Autodesk Fusion 360 part; units mm, degrees
(part 4 of 4)
ref_plane "工作平面8" through (0, 0, 210) normal (0, 0, 1) x (1, 0, 0) in component "10_CPU_140_FAN_MOUNT"
sketch "草图8 (20)" plane through (0, 0, 210) normal (0, 0, 1) x (1, 0, 0) in component "10_CPU_140_FAN_MOUNT"
  circle A0 centre (176.4, -14) radius 1.7
extrude "M3x6 fan panel tab clearance'" cut sketch "草图8 (20)" along normal blind 3.01 bodies 2 in component "10_CPU_140_FAN_MOUNT"
ref_plane "工作平面18" through (0, 0, 148) normal (0, 0, 1) x (1, 0, 0) in component "20_ONE_PIECE_DUAL_140_FAN_RAIL_284mm"
sketch "草图18 (3)" plane through (0, 0, 148) normal (0, 0, 1) x (1, 0, 0) in component "20_ONE_PIECE_DUAL_140_FAN_RAIL_284mm"
  line L0 (170.4, -19) -> (182.4, -19)
  line L1 (182.4, -19) -> (182.4, -9)
  line L2 (182.4, -9) -> (170.4, -9)
  line L3 (170.4, -9) -> (170.4, -19)
extrude "Integral fan panel tab support pad (2)" add sketch "草图18 (3)" along normal blind 12 bodies 35 in component "20_ONE_PIECE_DUAL_140_FAN_RAIL_284mm"
ref_plane "工作平面19" through (0, 0, 153.5) normal (0, 0, 1) x (1, 0, 0) in component "20_ONE_PIECE_DUAL_140_FAN_RAIL_284mm"
sketch "草图19 (3)" plane through (0, 0, 153.5) normal (0, 0, 1) x (1, 0, 0) in component "20_ONE_PIECE_DUAL_140_FAN_RAIL_284mm"
  circle A0 centre (176.4, -14) radius 2.35
extrude "H4.5 insert for fan panel M3x6 fastening (2)" cut sketch "草图19 (3)" along normal blind 6.51 bodies 35 in component "20_ONE_PIECE_DUAL_140_FAN_RAIL_284mm"
ref_plane "工作平面9" through (0, 0, 210) normal (0, 0, 1) x (1, 0, 0) in component "10_CPU_140_FAN_MOUNT"
sketch "草图9 (20)" plane through (0, 0, 210) normal (0, 0, 1) x (1, 0, 0) in component "10_CPU_140_FAN_MOUNT"
  line L0 (270.4, -19) -> (282.4, -19)
  line L1 (282.4, -19) -> (282.4, -9)
  line L2 (282.4, -9) -> (270.4, -9)
  line L3 (270.4, -9) -> (270.4, -19)
extrude "Integral 3 mm fan panel fastening tab (1)'" add sketch "草图9 (20)" along normal blind 3 bodies 2 in component "10_CPU_140_FAN_MOUNT"
ref_plane "工作平面10" through (0, 0, 210) normal (0, 0, 1) x (1, 0, 0) in component "10_CPU_140_FAN_MOUNT"
sketch "草图10 (17)" plane through (0, 0, 210) normal (0, 0, 1) x (1, 0, 0) in component "10_CPU_140_FAN_MOUNT"
  circle A0 centre (276.4, -14) radius 1.7
extrude "M3x6 fan panel tab clearance (1)'" cut sketch "草图10 (17)" along normal blind 3.01 bodies 2 in component "10_CPU_140_FAN_MOUNT"
ref_plane "工作平面20" through (0, 0, 148) normal (0, 0, 1) x (1, 0, 0) in component "20_ONE_PIECE_DUAL_140_FAN_RAIL_284mm"
sketch "草图20 (3)" plane through (0, 0, 148) normal (0, 0, 1) x (1, 0, 0) in component "20_ONE_PIECE_DUAL_140_FAN_RAIL_284mm"
  line L0 (270.4, -19) -> (282.4, -19)
  line L1 (282.4, -19) -> (282.4, -9)
  line L2 (282.4, -9) -> (270.4, -9)
  line L3 (270.4, -9) -> (270.4, -19)
extrude "Integral fan panel tab support pad (3)" add sketch "草图20 (3)" along normal blind 12 bodies 35 in component "20_ONE_PIECE_DUAL_140_FAN_RAIL_284mm"
ref_plane "工作平面21" through (0, 0, 153.5) normal (0, 0, 1) x (1, 0, 0) in component "20_ONE_PIECE_DUAL_140_FAN_RAIL_284mm"
sketch "草图21 (3)" plane through (0, 0, 153.5) normal (0, 0, 1) x (1, 0, 0) in component "20_ONE_PIECE_DUAL_140_FAN_RAIL_284mm"
  circle A0 centre (276.4, -14) radius 2.35
extrude "H4.5 insert for fan panel M3x6 fastening (3)" cut sketch "草图21 (3)" along normal blind 6.51 bodies 35 in component "20_ONE_PIECE_DUAL_140_FAN_RAIL_284mm"
ref_plane "工作平面38" through (0, -263, 0) normal (0, 1, 0) x (0, 0, 1) in component "07_GPU_REINFORCED_REAR_TOWER"
sketch "草图38" plane through (0, -263, 0) normal (0, 1, 0) x (1, 0, 0) in component "07_GPU_REINFORCED_REAR_TOWER"
  circle A0 through (84.1, -262, 526) (77.95, -258.4493, 526) (77.95, -265.5507, 526)
extrude "V14 accessible mushroom head channel end" cut sketch "草图38" along normal blind 24 contours A0 in plane through (0, 263, 0) normal (0, 1, 0) bodies 26 in component "07_GPU_REINFORCED_REAR_TOWER"
ref_plane "工作平面39" through (0, -263, 0) normal (0, 1, 0) x (0, 0, 1) in component "07_GPU_REINFORCED_REAR_TOWER"
sketch "草图39" plane through (0, -263, 0) normal (0, 1, 0) x (1, 0, 0) in component "07_GPU_REINFORCED_REAR_TOWER"
  circle A0 through (84.1, -292, 526) (77.95, -288.4493, 526) (77.95, -295.5507, 526)
extrude "V14 accessible mushroom head channel end (1)" cut sketch "草图39" along normal blind 24 contours A0 in plane through (0, 263, 0) normal (0, 1, 0) bodies 26 in component "07_GPU_REINFORCED_REAR_TOWER"
ref_plane "工作平面40" through (0, 0, 262) normal (0, 0, 1) x (1, 0, 0) in component "07_GPU_REINFORCED_REAR_TOWER"
sketch "草图40" plane through (0, 0, 262) normal (0, 0, 1) x (1, 0, 0) in component "07_GPU_REINFORCED_REAR_TOWER"
  line L0 (75.9, 263) -> (84.1, 263)
  line L1 (84.1, 263) -> (84.1, 287)
  line L2 (84.1, 287) -> (75.9, 287)
  line L3 (75.9, 287) -> (75.9, 263)
extrude "V14 accessible mushroom head channel web" cut sketch "草图40" along normal blind 30 bodies 26 in component "07_GPU_REINFORCED_REAR_TOWER"
ref_plane "工作平面41" through (0, -263, 0) normal (0, 1, 0) x (0, 0, 1) in component "07_GPU_REINFORCED_REAR_TOWER"
sketch "草图41" plane through (0, -263, 0) normal (0, 1, 0) x (1, 0, 0) in component "07_GPU_REINFORCED_REAR_TOWER"
  circle A0 through (84.1, -157, 526) (77.95, -153.4493, 526) (77.95, -160.5507, 526)
extrude "V14 accessible mushroom head channel end (2)" cut sketch "草图41" along normal blind 24 contours A0 in plane through (0, 263, 0) normal (0, 1, 0) bodies 26 in component "07_GPU_REINFORCED_REAR_TOWER"
ref_plane "工作平面42" through (0, -263, 0) normal (0, 1, 0) x (0, 0, 1) in component "07_GPU_REINFORCED_REAR_TOWER"
sketch "草图42" plane through (0, -263, 0) normal (0, 1, 0) x (1, 0, 0) in component "07_GPU_REINFORCED_REAR_TOWER"
  circle A0 through (84.1, -165, 526) (77.95, -161.4493, 526) (77.95, -168.5507, 526)
extrude "V14 accessible mushroom head channel end (3)" cut sketch "草图42" along normal blind 24 contours A0 in plane through (0, 263, 0) normal (0, 1, 0) bodies 26 in component "07_GPU_REINFORCED_REAR_TOWER"
ref_plane "工作平面43" through (0, 0, 157) normal (0, 0, 1) x (1, 0, 0) in component "07_GPU_REINFORCED_REAR_TOWER"
sketch "草图43" plane through (0, 0, 157) normal (0, 0, 1) x (1, 0, 0) in component "07_GPU_REINFORCED_REAR_TOWER"
  line L0 (75.9, 263) -> (84.1, 263)
  line L1 (84.1, 263) -> (84.1, 287)
  line L2 (84.1, 287) -> (75.9, 287)
  line L3 (75.9, 287) -> (75.9, 263)
extrude "V14 accessible mushroom head channel web (1)" cut sketch "草图43" along normal blind 8 bodies 26 in component "07_GPU_REINFORCED_REAR_TOWER"
ref_plane "工作平面44" through (0, -263, 0) normal (0, 1, 0) x (0, 0, 1) in component "07_GPU_REINFORCED_REAR_TOWER"
sketch "草图44" plane through (0, -263, 0) normal (0, 1, 0) x (1, 0, 0) in component "07_GPU_REINFORCED_REAR_TOWER"
  circle A0 through (168.1, -262, 526) (161.95, -258.4493, 526) (161.95, -265.5507, 526)
extrude "V14 accessible mushroom head channel end (4)" cut sketch "草图44" along normal blind 24 contours A0 in plane through (0, 263, 0) normal (0, 1, 0) bodies 26 in component "07_GPU_REINFORCED_REAR_TOWER"
ref_plane "工作平面45" through (0, -263, 0) normal (0, 1, 0) x (0, 0, 1) in component "07_GPU_REINFORCED_REAR_TOWER"
sketch "草图45" plane through (0, -263, 0) normal (0, 1, 0) x (1, 0, 0) in component "07_GPU_REINFORCED_REAR_TOWER"
  circle A0 through (168.1, -292, 526) (161.95, -288.4493, 526) (161.95, -295.5507, 526)
extrude "V14 accessible mushroom head channel end (5)" cut sketch "草图45" along normal blind 24 contours A0 in plane through (0, 263, 0) normal (0, 1, 0) bodies 26 in component "07_GPU_REINFORCED_REAR_TOWER"
ref_plane "工作平面46" through (0, 0, 262) normal (0, 0, 1) x (1, 0, 0) in component "07_GPU_REINFORCED_REAR_TOWER"
sketch "草图46" plane through (0, 0, 262) normal (0, 0, 1) x (1, 0, 0) in component "07_GPU_REINFORCED_REAR_TOWER"
  line L0 (159.9, 263) -> (168.1, 263)
  line L1 (168.1, 263) -> (168.1, 287)
  line L2 (168.1, 287) -> (159.9, 287)
  line L3 (159.9, 287) -> (159.9, 263)
extrude "V14 accessible mushroom head channel web (2)" cut sketch "草图46" along normal blind 30 bodies 26 in component "07_GPU_REINFORCED_REAR_TOWER"
ref_plane "工作平面47" through (0, -263, 0) normal (0, 1, 0) x (0, 0, 1) in component "07_GPU_REINFORCED_REAR_TOWER"
sketch "草图47" plane through (0, -263, 0) normal (0, 1, 0) x (1, 0, 0) in component "07_GPU_REINFORCED_REAR_TOWER"
  circle A0 through (168.1, -157, 526) (161.95, -153.4493, 526) (161.95, -160.5507, 526)
extrude "V14 accessible mushroom head channel end (6)" cut sketch "草图47" along normal blind 24 contours A0 in plane through (0, 263, 0) normal (0, 1, 0) bodies 26 in component "07_GPU_REINFORCED_REAR_TOWER"
ref_plane "工作平面48" through (0, -263, 0) normal (0, 1, 0) x (0, 0, 1) in component "07_GPU_REINFORCED_REAR_TOWER"
sketch "草图48" plane through (0, -263, 0) normal (0, 1, 0) x (1, 0, 0) in component "07_GPU_REINFORCED_REAR_TOWER"
  circle A0 through (168.1, -165, 526) (161.95, -161.4493, 526) (161.95, -168.5507, 526)
extrude "V14 accessible mushroom head channel end (7)" cut sketch "草图48" along normal blind 24 contours A0 in plane through (0, 263, 0) normal (0, 1, 0) bodies 26 in component "07_GPU_REINFORCED_REAR_TOWER"
ref_plane "工作平面49" through (0, 0, 157) normal (0, 0, 1) x (1, 0, 0) in component "07_GPU_REINFORCED_REAR_TOWER"
sketch "草图49" plane through (0, 0, 157) normal (0, 0, 1) x (1, 0, 0) in component "07_GPU_REINFORCED_REAR_TOWER"
  line L0 (159.9, 263) -> (168.1, 263)
  line L1 (168.1, 263) -> (168.1, 287)
  line L2 (168.1, 287) -> (159.9, 287)
  line L3 (159.9, 287) -> (159.9, 263)
extrude "V14 accessible mushroom head channel web (3)" cut sketch "草图49" along normal blind 8 bodies 26 in component "07_GPU_REINFORCED_REAR_TOWER"
ref_plane "工作平面50" through (0, 0, 143) normal (0, 0, 1) x (1, 0, 0) in component "07_GPU_REINFORCED_REAR_TOWER"
sketch "草图50" plane through (0, 0, 143) normal (0, 0, 1) x (1, 0, 0) in component "07_GPU_REINFORCED_REAR_TOWER"
  circle A0 centre (80, 248.5) radius 4.1
extrude "V14 8.2 mm tower base mushroom head well" cut sketch "草图50" along normal blind 5.01 bodies 26 in component "07_GPU_REINFORCED_REAR_TOWER"
ref_plane "工作平面51" through (0, 0, 143) normal (0, 0, 1) x (1, 0, 0) in component "07_GPU_REINFORCED_REAR_TOWER"
sketch "草图51" plane through (0, 0, 143) normal (0, 0, 1) x (1, 0, 0) in component "07_GPU_REINFORCED_REAR_TOWER"
  circle A0 centre (140, 248.5) radius 4.1
extrude "V14 8.2 mm tower base mushroom head well (1)" cut sketch "草图51" along normal blind 5.01 bodies 26 in component "07_GPU_REINFORCED_REAR_TOWER"
ref_plane "工作平面52" through (0, 0, 143) normal (0, 0, 1) x (1, 0, 0) in component "07_GPU_REINFORCED_REAR_TOWER"
sketch "草图52" plane through (0, 0, 143) normal (0, 0, 1) x (1, 0, 0) in component "07_GPU_REINFORCED_REAR_TOWER"
  circle A0 centre (158, 248.5) radius 4.1
extrude "V14 8.2 mm tower base mushroom head well (2)" cut sketch "草图52" along normal blind 5.01 bodies 26 in component "07_GPU_REINFORCED_REAR_TOWER"
ref_plane "工作平面11" through (0, 0, 272) normal (0, 0, 1) x (1, 0, 0) in component "08_GPU_UPPER_EAR_LEDGE_ADJUSTABLE"
sketch "草图11 (14)" plane through (0, 0, 272) normal (0, 0, 1) x (1, 0, 0) in component "08_GPU_UPPER_EAR_LEDGE_ADJUSTABLE"
  line L0 (84, 241.84) -> (154, 241.84)
  line L1 (154, 241.84) -> (154, 244.85)
  line L2 (154, 244.85) -> (84, 244.85)
  line L3 (84, 244.85) -> (84, 241.84)
ref_plane "工作平面12" through (0, 0, 275.5) normal (0, 0, 1) x (1, 0, 0) in component "08_GPU_UPPER_EAR_LEDGE_ADJUSTABLE"
sketch "草图12 (10)" plane through (0, 0, 275.5) normal (0, 0, 1) x (1, 0, 0) in component "08_GPU_UPPER_EAR_LEDGE_ADJUSTABLE"
  circle A0 centre (100, 246.5) radius 2.35
ref_plane "工作平面13" through (0, 0, 275.5) normal (0, 0, 1) x (1, 0, 0) in component "08_GPU_UPPER_EAR_LEDGE_ADJUSTABLE"
sketch "草图13 (9)" plane through (0, 0, 275.5) normal (0, 0, 1) x (1, 0, 0) in component "08_GPU_UPPER_EAR_LEDGE_ADJUSTABLE"
  circle A0 centre (120, 246.5) radius 2.35
ref_plane "工作平面14" through (0, 0, 271.99) normal (0, 0, 1) x (1, 0, 0) in component "08_GPU_UPPER_EAR_LEDGE_ADJUSTABLE"
sketch "草图14 (9)" plane through (0, 0, 271.99) normal (0, 0, 1) x (1, 0, 0) in component "08_GPU_UPPER_EAR_LEDGE_ADJUSTABLE"
  line L0 (83.99, 241.83) -> (154.01, 241.83)
  line L1 (154.01, 241.83) -> (154.01, 242.84)
  line L2 (154.01, 242.84) -> (83.99, 242.84)
  line L3 (83.99, 242.84) -> (83.99, 241.83)
ref_plane "工作平面15" through (0, 0, 261.99) normal (0, 0, 1) x (1, 0, 0) in component "08_GPU_UPPER_EAR_LEDGE_ADJUSTABLE"
sketch "草图15 (7)" plane through (0, 0, 261.99) normal (0, 0, 1) x (1, 0, 0) in component "08_GPU_UPPER_EAR_LEDGE_ADJUSTABLE"
  line L0 (83.99, 244.83) -> (154.01, 244.83)
  line L1 (154.01, 244.83) -> (154.01, 246.84)
  line L2 (154.01, 246.84) -> (83.99, 246.84)
  line L3 (83.99, 246.84) -> (83.99, 244.83)
extrude "V16 retract original ear platform front 2 mm including projecting gussets" cut sketch "草图15 (7)" along normal blind 20.02 bodies 27 in component "08_GPU_UPPER_EAR_LEDGE_ADJUSTABLE"
ref_plane "工作平面16" through (0, 0, 275.5) normal (0, 0, 1) x (1, 0, 0) in component "08_GPU_UPPER_EAR_LEDGE_ADJUSTABLE"
sketch "草图16 (6)" plane through (0, 0, 275.5) normal (0, 0, 1) x (1, 0, 0) in component "08_GPU_UPPER_EAR_LEDGE_ADJUSTABLE"
  circle A0 centre (100, 251) radius 2.35
extrude "V16 ear M3 short insert Y251" cut sketch "草图16 (6)" along normal blind 6.5 bodies 27 in component "08_GPU_UPPER_EAR_LEDGE_ADJUSTABLE"
ref_plane "工作平面17" through (0, 0, 275.5) normal (0, 0, 1) x (1, 0, 0) in component "08_GPU_UPPER_EAR_LEDGE_ADJUSTABLE"
sketch "草图17 (4)" plane through (0, 0, 275.5) normal (0, 0, 1) x (1, 0, 0) in component "08_GPU_UPPER_EAR_LEDGE_ADJUSTABLE"
  circle A0 centre (120, 251) radius 2.35
extrude "V16 ear M3 short insert Y251 (1)" cut sketch "草图17 (4)" along normal blind 6.5 bodies 27 in component "08_GPU_UPPER_EAR_LEDGE_ADJUSTABLE"
ref_plane "工作平面53" through (0, 0, 139.99) normal (0, 0, 1) x (1, 0, 0) in component "07_GPU_REINFORCED_REAR_TOWER"
sketch "草图53" plane through (0, 0, 139.99) normal (0, 0, 1) x (1, 0, 0) in component "07_GPU_REINFORCED_REAR_TOWER"
  line L0 (150, 243.99) -> (174.01, 243.99)
  line L1 (174.01, 243.99) -> (174.01, 254)
  line L2 (174.01, 254) -> (150, 254)
  line L3 (150, 254) -> (150, 243.99)
extrude "V16 shorten CPU-side forward foot 24 mm and remove inaccessible X158 screw" cut sketch "草图53" along normal blind 8.011 bodies 26 in component "07_GPU_REINFORCED_REAR_TOWER"
ref_plane "工作平面10" through (0, 0, 147.99) normal (0, 0, 1) x (1, 0, 0) in component "08_GPU_LOWER_TWO_TAB_RECEIVER_ADJUSTABLE"
sketch "草图10 (18)" plane through (0, 0, 147.99) normal (0, 0, 1) x (1, 0, 0) in component "08_GPU_LOWER_TWO_TAB_RECEIVER_ADJUSTABLE"
  line L0 (132, 244.83) -> (140.01, 244.83)
  line L1 (140.01, 244.83) -> (140.01, 254)
  line L2 (140.01, 254) -> (132, 254)
  line L3 (132, 254) -> (132, 244.83)
extrude "V16 shorten lower tab guide to X132 for second base screw access" cut sketch "草图10 (18)" along normal blind 10.02 bodies 28 in component "08_GPU_LOWER_TWO_TAB_RECEIVER_ADJUSTABLE"
ref_plane "工作平面11" through (0, 0, 147.99) normal (0, 0, 1) x (1, 0, 0) in component "08_GPU_LOWER_TWO_TAB_RECEIVER_ADJUSTABLE"
sketch "草图11 (15)" plane through (0, 0, 147.99) normal (0, 0, 1) x (1, 0, 0) in component "08_GPU_LOWER_TWO_TAB_RECEIVER_ADJUSTABLE"
  line L0 (83.99, 244.83) -> (85, 244.83)
  line L1 (85, 244.83) -> (85, 254)
  line L2 (85, 254) -> (83.99, 254)
  line L3 (83.99, 254) -> (83.99, 244.83)
extrude "V16 clear opposite base screw head entry at X80" cut sketch "草图11 (15)" along normal blind 10.02 bodies 28 in component "08_GPU_LOWER_TWO_TAB_RECEIVER_ADJUSTABLE"
component "10_GPU_140_FAN_MOUNT" placed x (1, 0, 0) y (0, 1, 0) z (0, 0, 1) at (0, 0, -50)
component "10_CPU_140_FAN_MOUNT" placed x (1, 0, 0) y (0, 1, 0) z (0, 0, 1) at (0, 0, -50)
component "REF_CASE_FAN_GPU_140x140x25" placed x (1, 0, 0) y (0, 1, 0) z (0, 0, 1) at (0, 0, -50)
component "REF_AIRFLOW_GPU_FRONT_TO_REAR" placed x (1, 0, 0) y (0, 1, 0) z (0, 0, 1) at (0, 0, -50)
component "REF_CASE_FAN_CPU_140x140x25" placed x (1, 0, 0) y (0, 1, 0) z (0, 0, 1) at (0, 0, -50)
component "REF_AIRFLOW_CPU_FRONT_TO_REAR" placed x (1, 0, 0) y (0, 1, 0) z (0, 0, 1) at (0, 0, -50)
component "REF_BOARD_304.8x243.84_NUMBERED_HOLES" placed x (1, 0, 0) y (0, 1, 0) z (0, 0, 1) at (0, 0, -50)
component "REF_CPU_RIGHT" placed x (1, 0, 0) y (0, 1, 0) z (0, 0, 1) at (0, 0, -50)
component "REF_MEMORY_RIGHT_FRONT" placed x (1, 0, 0) y (0, 1, 0) z (0, 0, 1) at (0, 0, -50)
component "REF_PRIMARY_PCIE_X126.4_APPROX" placed x (1, 0, 0) y (0, 1, 0) z (0, 0, 1) at (0, 0, -50)
component "REF_SECOND_LONG_PCIE_X60_APPROX" placed x (1, 0, 0) y (0, 1, 0) z (0, 0, 1) at (0, 0, -50)
component "REF_GPU_FANS_TO_MINUS_X" placed x (1, 0, 0) y (0, 1, 0) z (0, 0, 1) at (0, 0, -50)
component "REF_GPU_FAN_MARKERS_MINUS_X" placed x (1, 0, 0) y (0, 1, 0) z (0, 0, 1) at (0, 0, -50)
component "04_front_GROUND_BAR_290mm_FLAT_PSU" placed x (1, 0, 0) y (0, 1, 0) z (0, 0, 1) at (0, 0, 0)
component "04_rear_GROUND_BAR_290mm_FLAT_PSU" placed x (1, 0, 0) y (0, 1, 0) z (0, 0, 1) at (0, 0, 0)
component "05_CENTERED_FLAT_PSU_CRADLE_OPEN_INTAKE" placed x (1, 0, 0) y (0, 1, 0) z (0, 0, 1) at (0, 0, 0)
component "REF_PSU_FLAT_CENTERED_150x140x86" placed x (1, 0, 0) y (0, 1, 0) z (0, 0, 1) at (0, 0, 0)
component "REF_PSU_INTAKE_DOWN_MINUS_Z" placed x (1, 0, 0) y (0, 1, 0) z (0, 0, 1) at (0, 0, 0)
component "REF_PSU_REAR_EXHAUST_PLUS_Y" placed x (1, 0, 0) y (0, 1, 0) z (0, 0, 1) at (0, 0, 0)
component "12_front_PCI_SUPPORT_FRAME" placed x (1, 0, 0) y (0, 1, 0) z (0, 0, 1) at (0, 0, 0)
component "12_front_CPU_SUPPORT_FRAME" placed x (1, 0, 0) y (0, 1, 0) z (0, 0, 1) at (0, 0, 0)
component "07_GPU_REINFORCED_REAR_TOWER" placed x (1, 0, 0) y (0, 1, 0) z (0, 0, 1) at (0, 0, 0)
component "08_GPU_UPPER_EAR_LEDGE_ADJUSTABLE" placed x (1, 0, 0) y (0, 1, 0) z (0, 0, 1) at (0, 0, 0)
component "08_GPU_LOWER_TWO_TAB_RECEIVER_ADJUSTABLE" placed x (1, 0, 0) y (0, 1, 0) z (0, 0, 1) at (0, 0, 0)
component "16_CPU_VERTICAL_SIDE_FLUSH_TO_BEAM" placed x (1, 0, 0) y (0, 1, 0) z (0, 0, 1) at (0, 0, 0)
component "16_PCI_INSET_SIDE_16_45mm" placed x (1, 0, 0) y (0, 1, 0) z (0, 0, 1) at (0, 0, 0)
component "19_PCI_LONGITUDINAL_BOARD_RAIL_243_84mm" placed x (1, 0, 0) y (0, 1, 0) z (0, 0, 1) at (0, 0, 0)
component "19_MID_LONGITUDINAL_BOARD_RAIL_243_84mm" placed x (1, 0, 0) y (0, 1, 0) z (0, 0, 1) at (0, 0, 0)
component "19_CPU_LONGITUDINAL_BOARD_RAIL_243_84mm" placed x (1, 0, 0) y (0, 1, 0) z (0, 0, 1) at (0, 0, 0)
component "18_ONE_PIECE_REAR_LOAD_BEAM_304_45mm" placed x (1, 0, 0) y (0, 1, 0) z (0, 0, 1) at (0, 0, 0)
component "20_ONE_PIECE_DUAL_140_FAN_RAIL_284mm" placed x (1, 0, 0) y (0, 1, 0) z (0, 0, 1) at (0, 0, 0)
equation "desk_limit = 290 mm" comment "V03 layout review; fixed profiles require regeneration"
equation "footprint_width = 290 mm" comment "V03 layout review; fixed profiles require regeneration"
equation "board_width = 304.8 mm" comment "V03 layout review; fixed profiles require regeneration"
equation "board_depth = 243.84 mm" comment "V03 layout review; fixed profiles require regeneration"
equation "board_bottom_height = 208 mm" comment "V03 layout review; fixed profiles require regeneration"
equation "approx_slot_x = 126.4 mm" comment "V03 layout review; fixed profiles require regeneration"
equation "v13_rear_overall_length = 304.45 mm" comment "V13 manufacturing reference; geometry controlled by named feature sketches"
equation "v13_fan_rail_length = 284 mm" comment "V13 manufacturing reference; geometry controlled by named feature sketches"
equation "v13_bed_side = 256 mm" comment "V13 manufacturing reference; geometry controlled by named feature sketches"
equation "v13_insert_pilot = 4.7 mm" comment "V13 manufacturing reference; geometry controlled by named feature sketches"
equation "v13_screw_clearance = 3.4 mm" comment "V13 manufacturing reference; geometry controlled by named feature sketches"
equation "v13_head_well = 6.6 mm" comment "V13 manufacturing reference; geometry controlled by named feature sketches"
equation "v14_gpu_head_channel = 8.2 mm" comment "Nominal; compensate observed 0.6 mm undersize; physical retest required"
equation "v14_gpu_ear_offset = 3 mm" comment "Upper holes and platform front extended towards minus Y"
equation "v15_platform_extension = 2 mm" comment "User revised platform only; upper insert centres unchanged"
equation "v16_ear_front_retraction = 2 mm" comment "From original V13 front; vertical thickness remains 10 mm"
equation "v16_ear_hole_rear_offset = 1.5 mm" comment "From original V13 hole centres, towards tower"
equation "v16_lower_guide_right_x = 132 mm" comment "Expose X140 base screw; preserve both GPU metal tab slots"
equation "v16_forward_foot_right_x = 150 mm" comment "First X158 base screw omitted; tower rear supports retained"
